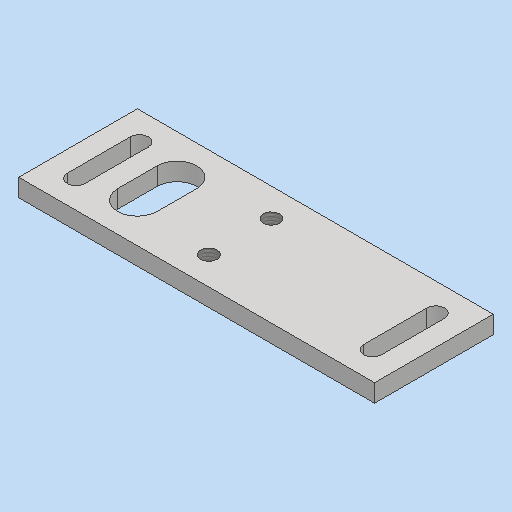
# Autodesk Inventor part: MM0948AN140_G01_107
Saved by Autodesk Inventor 2023.3 (Build 273359000, 359)
## iProperties
RuleStatus: InUse
Created: 2023-03-23
Part Number: MM0948AN140_G01_107
Project: 0850
Material: 1.0038 S235JRG2
Description: =<RBPARTNOTITLE2>
Document SubType Name: Modeling
Designer: dieter.david
Mass: 81.9118 g
Surface Area: 64.8111 cm^2
Volume: 10.4346 cm^3
Density: 7.85 g/cm^3
Appearance: silber AnP
AnP_Kategorie: 1
AnP_Material: =<Material>
MaxAbmaße: 4,5 x 30 x 90 (FM)
AnP_TemplVers: 20200821
RBDOCUMENTTYPE: DRF
RBDOCUMENTVERSION: 00
RBDRAWINGMAINSCALE: 1:1
RBDRAWINGMISSINGSPEC: --
RBDRAWINGVOLUME: --
RBDSV1: 0850
RBGBEDGESIN1: +0,5
RBGBEDGESIN2: +0,2
RBGBEDGESOUT1: -0,3
RBGBEDGESOUT2: -0,1
RBMATERIAL: =<Material>
RBMATMEETS: --
RBMATNO: =<Part Number>
RBPARTMADEOF: 4,5 x 30 x 90 (FM)
RBPARTNO: SIEHE MNR
RBPARTNOTITLE1: manufactured part
RBPARTNOTITLE2: Anfertigungsteil
RBPARTSAFETYINDICATOR: --
RBSURFACE: chemically nickel-coated
RBSURFACE2: chem. vernickelt
RBZEDGESNORM: ISO13715:2002-06
RBZGENDIMCLASS: m
RBZGENDIMNORM: ISO 2768-1:1989-11
RBZGENGEOCLASS: H
RBZGENGEONORM: ISO 2768-2:1989-11
RBZSURFACENORM: ISO13D2:2002-02
RBZTOLERANCENORM: ISO 14405-1:2010-12
Name: MM0867AN110_G20_130.ipt
AnP_Kommentar_aktuell: =<Comments>
AnP_Material_aktuell: =<Material>
Author: FH/Wi
Keywords: =<RBPARTMADEOF>
Comments: =<RBSURFACE2>
Revision Number: 01
Autodesk Inventor part; units mm, degrees
ref_plane "YZ Plane" through (0, 0, 0) normal (1, 0, 0) x (0, 1, 0)
ref_plane "XZ Plane" through (0, 0, 0) normal (0, 1, 0) x (-1, 0, 0)
ref_plane "XY Plane" through (0, 0, 0) normal (0, 0, 1) x (1, 0, 0)
sketch "Skizze1" plane through (0, 0, 0) normal (0, 0, 1) x (1, 0, 0)
  line L0 (-45, 15) -> (45, 15)
  line L1 (45, 15) -> (45, -15)
  line L2 (45, -15) -> (-45, -15)
  line L3 (-45, -15) -> (-45, 15)
  point P0 (0, 0)
  point P1 (45, 0)
  point P2 (0, 15)
  dimension "d0" = 30
  dimension "d1" = 90
  constraints: 8 end point, 2 midpoint, 2 parallel, 1 horizontal, 1 horizontal alignment, 1 perpendicular, 1 vertical alignment
  measures "d0" distance between parallel lines of L2 L0
  measures "d1" distance between parallel lines of L1 L3
extrude "Extrusion1" add sketch "Skizze1" along normal blind 4.5
sketch "Skizze2" plane through (0, 0, 4.5) normal (0, 0, 1) x (1, 0, 0)
  line L0 (-37.5, 8) -> (-37.5, -8) construction
  line L1 (-39.75, 8) -> (-39.75, -8)
  line L2 (-35.25, -8) -> (-35.25, 8)
  arc A0 (-35.25, 8) -> (-39.75, 8) centre (-37.5, 8) ccw
  arc A1 (-39.75, -8) -> (-35.25, -8) centre (-37.5, -8) ccw
  line L3 (37.5, 8) -> (37.5, -8) construction
  line L4 (35.25, 8) -> (35.25, -8)
  line L5 (39.75, -8) -> (39.75, 8)
  arc A2 (39.75, 8) -> (35.25, 8) centre (37.5, 8) ccw
  arc A3 (35.25, -8) -> (39.75, -8) centre (37.5, -8) ccw
  line L6 (-45, 15) -> (-45, -15) projected
  line L7 (45, -15) -> (45, 15) projected
  point P0 (0, 0)
  point P1 (-37.5, 0)
  point P2 (37.5, 0)
  dimension "d4" = 7.5
  dimension "d5" = 7.5
  dimension "d6" = 2.25
  dimension "d7" = 16
  constraints: 16 end point, 8 point on circle, 8 tangent, 4 centre point, 4 parallel, 2 horizontal alignment, 2 midpoint, 1 equal radius, 1 vertical
  measures "d4" distance between parallel lines of L0 L6
  measures "d5" distance between parallel lines of L7 L3
  measures "d6" radius of A1
  measures "d7" distance of L0.start L0.end
extrude "Extrusion2" cut sketch "Skizze2" against normal through all
sketch "Skizze3" plane through (0, 0, 4.5) normal (0, 0, 1) x (1, 0, 0)
  line L0 (45, -15) -> (45, 15) projected
  point P0 (0, 0)
  point P1 (-4, 7.9)
  point P2 (-4, -7.9)
  dimension "d10" = 49
  dimension "d11" = 15.8
  dimension "d12" = 7.9
  constraints: 1 vertical alignment
  measures "d10" distance from line of L0 point (-4, 7.9)
  measures "d11" distance of point (-4, 7.9) point (-4, -7.9)
  measures "d12" vertical distance of point (-4, 7.9) point (0, 0)
hole "Bohrung1" at (-4, 7.9, 4.5) at (-4, -7.9, 4.5) direction (0, 0, -1) diameter 4.134 end through all thread size "M5x0.8" designation "M5" class "6H" standard "ISO Metric profile"
sketch "Skizze4" plane through (0, 0, 4.5) normal (0, 0, 1) x (1, 0, 0)
  line L0 (-25, 5) -> (-25, -5) construction
  line L1 (-30, 5) -> (-30, -5)
  line L2 (-20, -5) -> (-20, 5)
  arc A0 (-20, 5) -> (-30, 5) centre (-25, 5) ccw
  arc A1 (-30, -5) -> (-20, -5) centre (-25, -5) ccw
  circle A2 centre (-4, -7.9) radius 2.067 projected
  point P0 (0, 0)
  point P1 (-25, 0)
  dimension "d20" = 21
  dimension "d21" = 5
  dimension "d22" = 10
  constraints: 8 end point, 4 point on circle, 4 tangent, 2 centre point, 1 horizontal alignment, 1 midpoint, 1 parallel, 1 vertical
  measures "d20" distance from line of A2.centre L0
  measures "d21" radius of A1
  measures "d22" distance of L0.start L0.end
extrude "Extrusion3" cut sketch "Skizze4" against normal through all contours A0 L2 A1 L1
equation "\"d5\" = d4"
equation "\"d12\" = 0.5 * d11"
